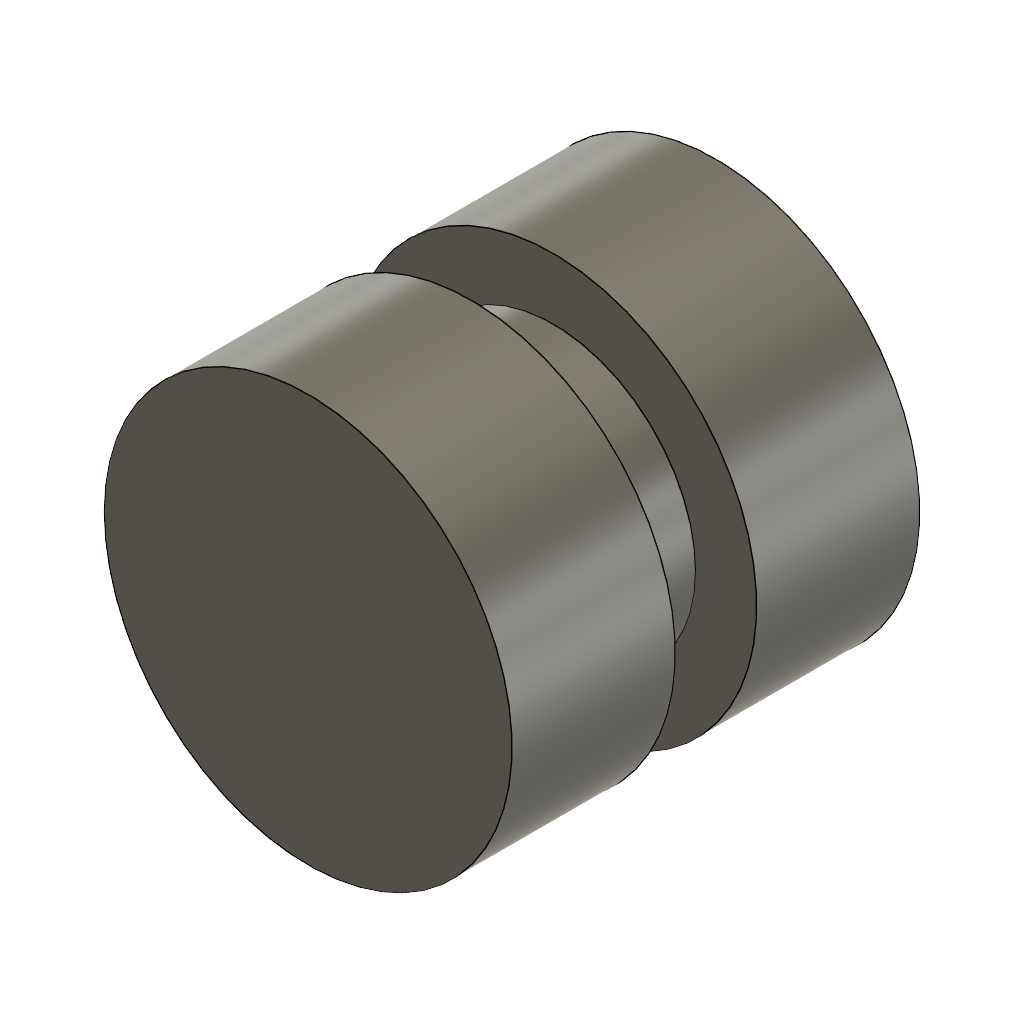
rev_cut_groove (Autodesk Fusion 360 design; units mm, degrees)
part number: 2026-11-13-14-41-15-703
Autodesk Fusion 360 part; units mm, degrees
sketch "Sketch1" plane through (0, 0, 0) normal (0, 0, 1) x (1, 0, 0)
  circle A0 centre (0, 0) radius 10
extrude "Extrude1" add sketch "Sketch1" along normal blind 20
sketch "Sketch2" plane through (0, 0, 0) normal (0, 1, 0) x (1, 0, 0)
  line L0 (7, -8) -> (12, -8)
  line L1 (12, -8) -> (12, -12)
  line L2 (12, -12) -> (7, -12)
  line L3 (7, -12) -> (7, -8)
revolve "Revolve1" cut sketch "Sketch2" angle 360 about axis through (0, 0, 1.75) along (0, 0, 1)
